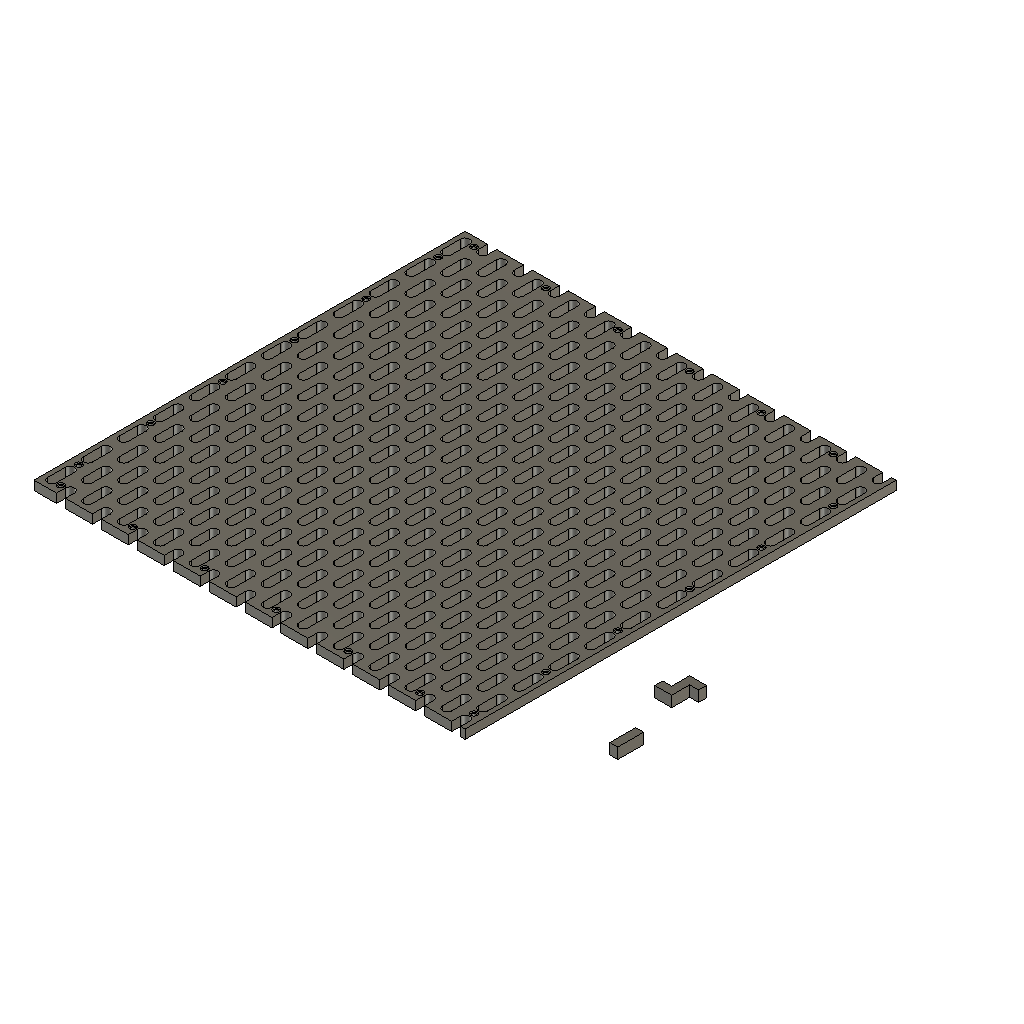
infinite-skadis-hd-v01 (Autodesk Fusion 360 design; units mm, degrees)
part number: 2026-10-27-12-40-24-664
part number: 2026-10-27-12-40-30-476
part number: 2026-10-27-12-43-59-311
part number: 2026-10-27-12-44-00-068
Autodesk Fusion 360 part; units mm, degrees
sketch "01 Panel envelope - constrained" plane through (0, 0, 0) normal (0, 0, 1) x (1, 0, 0) in component "Panel - dense staggered lattice"
  line L0 (0, 0) -> (240, 0)
  line L1 (240, 0) -> (240, 240)
  line L2 (240, 240) -> (0, 240)
  line L3 (0, 240) -> (0, 0)
  dimension "d18" = 240
  dimension "d19" = 240
  constraint coincident L0.start L3.end
  constraint horizontal L0
  constraint vertical L1
  constraint horizontal L2
  constraint vertical L3
  measures "d18" horizontal distance of L0.start L0.end
  measures "d19" vertical distance of L0.end L1.end
extrude "02 Face plate" add sketch "01 Panel envelope - constrained" along normal blind 5 makes body 1 in component "Panel - dense staggered lattice"
sketch "03 Slot A - constrained seed" plane through (0, 0, 0) normal (0, 0, 1) x (1, 0, 0) in component "Panel - dense staggered lattice"
  line L0 (7.5, 5) -> (7.5, 15)
  arc A0 (7.5, 15) -> (2.5, 15) centre (5, 15) ccw
  line L1 (2.5, 15) -> (2.5, 5)
  arc A1 (2.5, 5) -> (7.5, 5) centre (5, 5) ccw
  line L2 (5, 5) -> (5, 15) construction
  line L3 (5, 5) -> (15, 5) construction
  dimension "d22" = 5
  dimension "d23" = 10
  dimension "d24" = 90
  dimension "d25" = 5
  dimension "d26" = 5
  dimension "d44" = 10
  constraint tangent L0 A0
  constraint tangent A0 L1
  constraint tangent L1 A1
  constraint tangent L0 A1
  constraint parallel L0 L1
  constraint horizontal L3
  measures "d22" diameter of A0
  measures "d23" distance of A1.centre A0.centre
  measures "d24" angle of L2 L3
  measures "d25" horizontal distance of origin A1.centre
  measures "d26" vertical distance of origin A1.centre
  measures "d44" horizontal distance of A1.centre L3.end
extrude "04 Slot A through cut" cut sketch "03 Slot A - constrained seed" along normal blind 5 bodies 1 in component "Panel - dense staggered lattice"
pattern_linear "05 Lattice A" count 12 spacing 20 along (1, 0, 0) count 12 spacing 20 along (0, 1, 0) of "04 Slot A through cut" in component "Panel - dense staggered lattice"
sketch "03 Slot B - constrained seed" plane through (0, 0, 0) normal (0, 0, 1) x (1, 0, 0) in component "Panel - dense staggered lattice"
  line L0 (17.5, -5) -> (17.5, 5)
  arc A0 (17.5, 5) -> (12.5, 5) centre (15, 5) ccw
  line L1 (12.5, 5) -> (12.5, -5)
  arc A1 (12.5, -5) -> (17.5, -5) centre (15, -5) ccw
  line L2 (15, -5) -> (15, 5) construction
  line L3 (15, -5) -> (25, -5) construction
  dimension "d33" = 5
  dimension "d34" = 10
  dimension "d35" = 90
  dimension "d36" = 15
  dimension "d37" = 5
  dimension "d45" = 10
  constraint tangent L0 A0
  constraint tangent A0 L1
  constraint tangent L1 A1
  constraint tangent L0 A1
  constraint parallel L0 L1
  constraint horizontal L3
  measures "d33" diameter of A0
  measures "d34" distance of A1.centre A0.centre
  measures "d35" angle of L2 L3
  measures "d36" horizontal distance of origin A1.centre
  measures "d37" vertical distance of origin A1.centre
  measures "d45" horizontal distance of A1.centre L3.end
extrude "04 Slot B through cut" cut sketch "03 Slot B - constrained seed" along normal blind 5 bodies 1 in component "Panel - dense staggered lattice"
pattern_linear "05 Lattice B" count 12 spacing 20 along (1, 0, 0) count 13 spacing 20 along (0, 1, 0) of "04 Slot B through cut" in component "Panel - dense staggered lattice"
ref_plane "WorkPlane1" through (0, 0, 5) normal (0, 0, 1) x (1, 0, 0) in component "Panel - dense staggered lattice"
sketch "07 South visible screw clearance" plane through (0, 0, 0) normal (0, 0, 1) x (1, 0, 0) in component "Panel - dense staggered lattice"
  circle A0 centre (10, 5) radius 1.1
  dimension "d48" = 2.2
  dimension "d49" = 10
  dimension "d50" = 5
  measures "d48" diameter of A0
  measures "d49" horizontal distance of origin A0.centre
  measures "d50" vertical distance of origin A0.centre
extrude "08 South M2 through hole" cut sketch "07 South visible screw clearance" along normal blind 5 bodies 1 in component "Panel - dense staggered lattice"
sketch "09 South rear register" plane through (0, 0, 5) normal (0, 0, 1) x (1, 0, 0) in component "Panel - dense staggered lattice"
  circle A0 centre (10, 5) radius 1.8
  dimension "d53" = 3.6
  dimension "d54" = 10
  dimension "d55" = 5
  measures "d53" diameter of A0
  measures "d54" horizontal distance of origin A0.centre
  measures "d55" vertical distance of origin A0.centre
extrude "10 South locating pocket" cut sketch "09 South rear register" against normal blind 0.8 bodies 1 in component "Panel - dense staggered lattice"
pattern_linear "11 South 40 mm connector rhythm" count 6 spacing 40 along (1, 0, 0) count 3 spacing 0 along (1, 0, 0) of "08 South M2 through hole", "10 South locating pocket" in component "Panel - dense staggered lattice"
sketch "07 North visible screw clearance" plane through (0, 0, 0) normal (0, 0, 1) x (1, 0, 0) in component "Panel - dense staggered lattice"
  circle A0 centre (10, 235) radius 1.1
  dimension "d62" = 2.2
  dimension "d63" = 10
  dimension "d64" = 235
  measures "d62" diameter of A0
  measures "d63" horizontal distance of origin A0.centre
  measures "d64" vertical distance of origin A0.centre
extrude "08 North M2 through hole" cut sketch "07 North visible screw clearance" along normal blind 5 bodies 1 in component "Panel - dense staggered lattice"
sketch "09 North rear register" plane through (0, 0, 5) normal (0, 0, 1) x (1, 0, 0) in component "Panel - dense staggered lattice"
  circle A0 centre (10, 235) radius 1.8
  dimension "d67" = 3.6
  dimension "d68" = 10
  dimension "d69" = 235
  measures "d67" diameter of A0
  measures "d68" horizontal distance of origin A0.centre
  measures "d69" vertical distance of origin A0.centre
extrude "10 North locating pocket" cut sketch "09 North rear register" against normal blind 0.8 bodies 1 in component "Panel - dense staggered lattice"
pattern_linear "11 North 40 mm connector rhythm" count 6 spacing 40 along (1, 0, 0) count 3 spacing 0 along (1, 0, 0) of "08 North M2 through hole", "10 North locating pocket" in component "Panel - dense staggered lattice"
sketch "07 West visible screw clearance" plane through (0, 0, 0) normal (0, 0, 1) x (1, 0, 0) in component "Panel - dense staggered lattice"
  circle A0 centre (5, 20) radius 1.1
  dimension "d76" = 2.2
  dimension "d77" = 5
  dimension "d78" = 20
  measures "d76" diameter of A0
  measures "d77" horizontal distance of origin A0.centre
  measures "d78" vertical distance of origin A0.centre
extrude "08 West M2 through hole" cut sketch "07 West visible screw clearance" along normal blind 5 bodies 1 in component "Panel - dense staggered lattice"
sketch "09 West rear register" plane through (0, 0, 5) normal (0, 0, 1) x (1, 0, 0) in component "Panel - dense staggered lattice"
  circle A0 centre (5, 20) radius 1.8
  dimension "d81" = 3.6
  dimension "d82" = 5
  dimension "d83" = 20
  measures "d81" diameter of A0
  measures "d82" horizontal distance of origin A0.centre
  measures "d83" vertical distance of origin A0.centre
extrude "10 West locating pocket" cut sketch "09 West rear register" against normal blind 0.8 bodies 1 in component "Panel - dense staggered lattice"
pattern_linear "11 West 40 mm connector rhythm" count 6 spacing 40 along (0, 1, 0) count 3 spacing 0 along (0, 1, 0) of "08 West M2 through hole", "10 West locating pocket" in component "Panel - dense staggered lattice"
sketch "07 East visible screw clearance" plane through (0, 0, 0) normal (0, 0, 1) x (1, 0, 0) in component "Panel - dense staggered lattice"
  circle A0 centre (235, 10) radius 1.1
  dimension "d90" = 2.2
  dimension "d91" = 235
  dimension "d92" = 10
  measures "d90" diameter of A0
  measures "d91" horizontal distance of origin A0.centre
  measures "d92" vertical distance of origin A0.centre
extrude "08 East M2 through hole" cut sketch "07 East visible screw clearance" along normal blind 5 bodies 1 in component "Panel - dense staggered lattice"
sketch "09 East rear register" plane through (0, 0, 5) normal (0, 0, 1) x (1, 0, 0) in component "Panel - dense staggered lattice"
  circle A0 centre (235, 10) radius 1.8
  dimension "d95" = 3.6
  dimension "d96" = 235
  dimension "d97" = 10
  measures "d95" diameter of A0
  measures "d96" horizontal distance of origin A0.centre
  measures "d97" vertical distance of origin A0.centre
extrude "10 East locating pocket" cut sketch "09 East rear register" against normal blind 0.8 bodies 1 in component "Panel - dense staggered lattice"
pattern_linear "11 East 40 mm connector rhythm" count 6 spacing 40 along (0, 1, 0) count 3 spacing 0 along (0, 1, 0) of "08 East M2 through hole", "10 East locating pocket" in component "Panel - dense staggered lattice"
sketch "12 Straight bridge blank" plane through (0, 0, 0) normal (0, 0, 1) x (1, 0, 0) in component "Bridge H - straight"
  line L0 (7.8, -7.2) -> (12.2, -7.2)
  line L1 (12.2, -7.2) -> (12.2, 7.2)
  line L2 (12.2, 7.2) -> (7.8, 7.2)
  line L3 (7.8, 7.2) -> (7.8, -7.2)
  dimension "d104" = 7.8
  dimension "d105" = 7.2
  dimension "d106" = 4.4
  dimension "d107" = 14.4
  constraint horizontal L0
  constraint vertical L1
  constraint horizontal L2
  constraint vertical L3
  measures "d104" horizontal distance of origin L0.start
  measures "d105" vertical distance of origin L0.start
  measures "d106" horizontal distance of L0.start L0.end
  measures "d107" vertical distance of L0.end L1.end
extrude "12 Straight bridge blank extrusion" add sketch "12 Straight bridge blank" along normal blind 6 separate body makes body 2 in component "Bridge H - straight"
ref_plane "WorkPlane1" through (0, 0, -0.6) normal (0, 0, 1) x (1, 0, 0) in component "Bridge H - straight"
sketch "16 Registration peg 1" plane through (0, 0, 0) normal (0, 0, 1) x (1, 0, 0) in component "Bridge H - straight"
  circle A0 centre (10, -5) radius 1.6
  dimension "d112" = 3.2
  dimension "d113" = 10
  dimension "d114" = 5
  measures "d112" diameter of A0
  measures "d113" horizontal distance of origin A0.centre
  measures "d114" vertical distance of origin A0.centre
extrude "17 Registration peg" add sketch "16 Registration peg 1" against normal blind 0.6 bodies 2 in component "Bridge H - straight"
sketch "18 M2 pilot 1" plane through (0, 0, -0.6) normal (0, 0, 1) x (1, 0, 0) in component "Bridge H - straight"
  circle A0 centre (10, -5) radius 0.8
  dimension "d117" = 1.6
  dimension "d118" = 10
  dimension "d119" = 5
  measures "d117" diameter of A0
  measures "d118" horizontal distance of origin A0.centre
  measures "d119" vertical distance of origin A0.centre
extrude "19 Blind pilot into bridge" cut sketch "18 M2 pilot 1" along normal blind 4.6 bodies 2 in component "Bridge H - straight"
sketch "16 Registration peg 2" plane through (0, 0, 0) normal (0, 0, 1) x (1, 0, 0) in component "Bridge H - straight"
  circle A0 centre (10, 5) radius 1.6
  dimension "d122" = 3.2
  dimension "d123" = 10
  dimension "d124" = 5
  measures "d122" diameter of A0
  measures "d123" horizontal distance of origin A0.centre
  measures "d124" vertical distance of origin A0.centre
extrude "17 Registration peg (1)" add sketch "16 Registration peg 2" against normal blind 0.6 bodies 2 in component "Bridge H - straight"
sketch "18 M2 pilot 2" plane through (0, 0, -0.6) normal (0, 0, 1) x (1, 0, 0) in component "Bridge H - straight"
  circle A0 centre (10, 5) radius 0.8
  dimension "d127" = 1.6
  dimension "d128" = 10
  dimension "d129" = 5
  measures "d127" diameter of A0
  measures "d128" horizontal distance of origin A0.centre
  measures "d129" vertical distance of origin A0.centre
extrude "19 Blind pilot into bridge (1)" cut sketch "18 M2 pilot 2" along normal blind 4.6 bodies 2 in component "Bridge H - straight"
sketch "12 Spine" plane through (0, 0, 0) normal (0, 0, 1) x (1, 0, 0) in component "Bridge V - staggered"
  line L0 (-2.2, -7.2) -> (2.2, -7.2)
  line L1 (2.2, -7.2) -> (2.2, 7.2)
  line L2 (2.2, 7.2) -> (-2.2, 7.2)
  line L3 (-2.2, 7.2) -> (-2.2, -7.2)
  dimension "d132" = 2.2
  dimension "d133" = 7.2
  dimension "d134" = 4.4
  dimension "d135" = 14.4
  constraint horizontal L0
  constraint vertical L1
  constraint horizontal L2
  constraint vertical L3
  measures "d132" horizontal distance of origin L0.start
  measures "d133" vertical distance of origin L0.start
  measures "d134" horizontal distance of L0.start L0.end
  measures "d135" vertical distance of L0.end L1.end
extrude "12 Spine extrusion" add sketch "12 Spine" along normal blind 6 separate body makes body 3 in component "Bridge V - staggered"
sketch "13 Lower arm" plane through (0, 0, 0) normal (0, 0, 1) x (1, 0, 0) in component "Bridge V - staggered"
  line L0 (-7.2, -7.2) -> (2.2, -7.2)
  line L1 (2.2, -7.2) -> (2.2, -2.8)
  line L2 (2.2, -2.8) -> (-7.2, -2.8)
  line L3 (-7.2, -2.8) -> (-7.2, -7.2)
  dimension "d138" = 7.2
  dimension "d139" = 7.2
  dimension "d140" = 9.4
  dimension "d141" = 4.4
  constraint horizontal L0
  constraint vertical L1
  constraint horizontal L2
  constraint vertical L3
  measures "d138" horizontal distance of origin L0.start
  measures "d139" vertical distance of origin L0.start
  measures "d140" horizontal distance of L0.start L0.end
  measures "d141" vertical distance of L0.end L1.end
extrude "13 Lower arm extrusion" add sketch "13 Lower arm" along normal blind 6 bodies 3 in component "Bridge V - staggered"
sketch "14 Upper arm" plane through (0, 0, 0) normal (0, 0, 1) x (1, 0, 0) in component "Bridge V - staggered"
  line L0 (-2.2, 2.8) -> (7.2, 2.8)
  line L1 (7.2, 2.8) -> (7.2, 7.2)
  line L2 (7.2, 7.2) -> (-2.2, 7.2)
  line L3 (-2.2, 7.2) -> (-2.2, 2.8)
  dimension "d144" = 2.2
  dimension "d145" = 2.8
  dimension "d146" = 9.4
  dimension "d147" = 4.4
  constraint horizontal L0
  constraint vertical L1
  constraint horizontal L2
  constraint vertical L3
  measures "d144" horizontal distance of origin L0.start
  measures "d145" vertical distance of origin L0.start
  measures "d146" horizontal distance of L0.start L0.end
  measures "d147" vertical distance of L0.end L1.end
extrude "14 Upper arm extrusion" add sketch "14 Upper arm" along normal blind 6 bodies 3 in component "Bridge V - staggered"
ref_plane "WorkPlane1" through (0, 0, -0.6) normal (0, 0, 1) x (1, 0, 0) in component "Bridge V - staggered"
sketch "16 Registration peg 1 (2)" plane through (0, 0, 0) normal (0, 0, 1) x (1, 0, 0) in component "Bridge V - staggered"
  circle A0 centre (-5, -5) radius 1.6
  dimension "d152" = 3.2
  dimension "d153" = 5
  dimension "d154" = 5
  measures "d152" diameter of A0
  measures "d153" horizontal distance of origin A0.centre
  measures "d154" vertical distance of origin A0.centre
extrude "17 Registration peg'" add sketch "16 Registration peg 1 (2)" against normal blind 0.6 bodies 3 in component "Bridge V - staggered"
sketch "18 M2 pilot 1 (2)" plane through (0, 0, -0.6) normal (0, 0, 1) x (1, 0, 0) in component "Bridge V - staggered"
  circle A0 centre (-5, -5) radius 0.8
  dimension "d157" = 1.6
  dimension "d158" = 5
  dimension "d159" = 5
  measures "d157" diameter of A0
  measures "d158" horizontal distance of origin A0.centre
  measures "d159" vertical distance of origin A0.centre
extrude "19 Blind pilot into bridge'" cut sketch "18 M2 pilot 1 (2)" along normal blind 4.6 bodies 3 in component "Bridge V - staggered"
sketch "16 Registration peg 2 (2)" plane through (0, 0, 0) normal (0, 0, 1) x (1, 0, 0) in component "Bridge V - staggered"
  circle A0 centre (5, 5) radius 1.6
  dimension "d162" = 3.2
  dimension "d163" = 5
  dimension "d164" = 5
  measures "d162" diameter of A0
  measures "d163" horizontal distance of origin A0.centre
  measures "d164" vertical distance of origin A0.centre
extrude "17 Registration peg (1)'" add sketch "16 Registration peg 2 (2)" against normal blind 0.6 bodies 3 in component "Bridge V - staggered"
sketch "18 M2 pilot 2 (2)" plane through (0, 0, -0.6) normal (0, 0, 1) x (1, 0, 0) in component "Bridge V - staggered"
  circle A0 centre (5, 5) radius 0.8
  dimension "d167" = 1.6
  dimension "d168" = 5
  dimension "d169" = 5
  measures "d167" diameter of A0
  measures "d168" horizontal distance of origin A0.centre
  measures "d169" vertical distance of origin A0.centre
extrude "19 Blind pilot into bridge (1)'" cut sketch "18 M2 pilot 2 (2)" along normal blind 4.6 bodies 3 in component "Bridge V - staggered"
component "Panel - dense staggered lattice" placed x (1, 0, 0) y (0, 1, 0) z (0, 0, 1) at (0, 0, 0)
component "Bridge H - straight" placed x (1, 0, 0) y (0, 1, 0) z (0, 0, 1) at (280, 40, 0)
component "Bridge V - staggered" placed x (1, 0, 0) y (0, 1, 0) z (0, 0, 1) at (280, 80, 0)
equation "columns = 12" comment "Integer 20 mm cells across; use even values 4 to 14"
equation "rows = 12" comment "Integer 20 mm cells high; use even values 4 to 14"
equation "pitch = 20 mm" comment "Dense lattice repeat; keep 20 for IKEA-compatible subset"
equation "slotWidth = 5 mm" comment "Nominal community-measured slot width; fit-test"
equation "slotHeight = 15 mm" comment "Retain full size slots"
equation "boardThickness = 5 mm" comment "Initial hook engagement thickness; fit-test"
equation "panelWidth = columns * pitch" comment "Derived panel width, do not scale in slicer"
equation "panelHeight = rows * pitch" comment "Derived panel height"
equation "pilotDiameter = 1.6 mm" comment "M2 thread-forming pilot, test before production"
equation "pilotDepth = 4 mm" comment "Blind from rear"
equation "registerDiameter = 3.6 mm" comment "Rear locating recess"
equation "registerDepth = 0.8 mm" comment "Rear locating recess depth"
equation "bridgeThickness = 6 mm" comment "Rear connector thickness"
equation "bridgeWidth = 4.4 mm" comment "Fits 5 mm lattice corridors"
equation "pegDiameter = 3.2 mm" comment "Locating peg: 0.2 mm radial clearance"
equation "pegHeight = 0.6 mm" comment "Locating peg: 0.2 mm depth clearance"
equation "screwClearance = 2.2 mm" comment "M2 screw clearance"
equation "d18 = panelWidth"
equation "d19 = panelHeight"
equation "d20 = boardThickness"
equation "d22 = slotWidth"
equation "d23 = slotHeight - slotWidth"
equation "d25 = pitch / 4"
equation "d26 = pitch / 2 - ( slotHeight - slotWidth ) / 2"
equation "d27 = boardThickness"
equation "d29 = columns"
equation "d30 = rows"
equation "d31 = pitch"
equation "d32 = pitch"
equation "d33 = slotWidth"
equation "d34 = slotHeight - slotWidth"
equation "d36 = 3 * pitch / 4"
equation "d37 = ( slotHeight - slotWidth ) / 2"
equation "d38 = boardThickness"
equation "d40 = columns"
equation "d41 = rows + 1"
equation "d42 = pitch"
equation "d43 = pitch"
equation "d44 = pitch / 2"
equation "d45 = pitch / 2"
equation "d46 = boardThickness"
equation "d48 = screwClearance"
equation "d49 = pitch / 2"
equation "d50 = pitch / 4"
equation "d51 = boardThickness"
equation "d53 = registerDiameter"
equation "d54 = pitch / 2"
equation "d55 = pitch / 4"
equation "d56 = -registerDepth"
equation "d58 = columns / 2"
equation "d60 = 2 * pitch"
equation "d62 = screwClearance"
equation "d63 = pitch / 2"
equation "d64 = panelHeight - pitch / 4"
equation "d65 = boardThickness"
equation "d67 = registerDiameter"
equation "d68 = pitch / 2"
equation "d69 = panelHeight - pitch / 4"
equation "d70 = -registerDepth"
equation "d72 = columns / 2"
equation "d74 = 2 * pitch"
equation "d76 = screwClearance"
equation "d77 = pitch / 4"
equation "d78 = pitch"
equation "d79 = boardThickness"
equation "d81 = registerDiameter"
equation "d82 = pitch / 4"
equation "d83 = pitch"
equation "d84 = -registerDepth"
equation "d86 = rows / 2"
equation "d88 = 2 * pitch"
equation "d90 = screwClearance"
equation "d91 = panelWidth - pitch / 4"
equation "d92 = pitch / 2"
equation "d93 = boardThickness"
equation "d95 = registerDiameter"
equation "d96 = panelWidth - pitch / 4"
equation "d97 = pitch / 2"
equation "d98 = -registerDepth"
equation "d100 = rows / 2"
equation "d102 = 2 * pitch"
equation "d104 = pitch / 2 - bridgeWidth / 2"
equation "d105 = -( -pitch / 4 - bridgeWidth / 2 )"
equation "d106 = bridgeWidth"
equation "d107 = pitch / 2 + bridgeWidth"
equation "d108 = bridgeThickness"
equation "d110 = -pegHeight"
equation "d112 = pegDiameter"
equation "d113 = pitch / 2"
equation "d114 = -( -pitch / 4 )"
equation "d115 = -pegHeight"
equation "d117 = pilotDiameter"
equation "d118 = pitch / 2"
equation "d119 = -( -pitch / 4 )"
equation "d120 = pilotDepth + pegHeight"
equation "d122 = pegDiameter"
equation "d123 = pitch / 2"
equation "d124 = pitch / 4"
equation "d125 = -pegHeight"
equation "d127 = pilotDiameter"
equation "d128 = pitch / 2"
equation "d129 = pitch / 4"
equation "d130 = pilotDepth + pegHeight"
equation "d132 = -( -bridgeWidth / 2 )"
equation "d133 = -( -pitch / 4 - bridgeWidth / 2 )"
equation "d134 = bridgeWidth"
equation "d135 = pitch / 2 + bridgeWidth"
equation "d136 = bridgeThickness"
equation "d138 = -( -pitch / 4 - bridgeWidth / 2 )"
equation "d139 = -( -pitch / 4 - bridgeWidth / 2 )"
equation "d140 = pitch / 4 + bridgeWidth"
equation "d141 = bridgeWidth"
equation "d142 = bridgeThickness"
equation "d144 = -( -bridgeWidth / 2 )"
equation "d145 = pitch / 4 - bridgeWidth / 2"
equation "d146 = pitch / 4 + bridgeWidth"
equation "d147 = bridgeWidth"
equation "d148 = bridgeThickness"
equation "d150 = -pegHeight"
equation "d152 = pegDiameter"
equation "d153 = -( -pitch / 4 )"
equation "d154 = -( -pitch / 4 )"
equation "d155 = -pegHeight"
equation "d157 = pilotDiameter"
equation "d158 = -( -pitch / 4 )"
equation "d159 = -( -pitch / 4 )"
equation "d160 = pilotDepth + pegHeight"
equation "d162 = pegDiameter"
equation "d163 = pitch / 4"
equation "d164 = pitch / 4"
equation "d165 = -pegHeight"
equation "d167 = pilotDiameter"
equation "d168 = pitch / 4"
equation "d169 = pitch / 4"
equation "d170 = pilotDepth + pegHeight"
named bodies: "Panel", "Bridge H - straight", "Bridge V - staggered"
